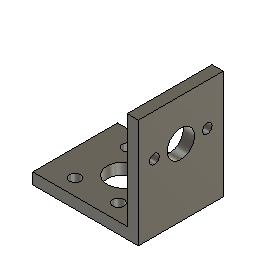
DC motor holder v2 (Autodesk Fusion 360 design; units mm, degrees)
part number: 2026-10-27-13-53-20-862
Autodesk Fusion 360 part; units mm, degrees
sketch "Sketch1" plane through (0, 0, 0) normal (0, 0, 1) x (1, 0, 0)
  line L0 (16.5, -13.25) -> (-16.5, -13.25)
  line L1 (-16.5, -13.25) -> (-16.5, 13.25)
  line L2 (-16.5, 13.25) -> (16.5, 13.25)
  line L3 (16.5, 13.25) -> (16.5, -13.25)
  line L4 (16.5, -13.25) -> (-16.5, 13.25) construction
  line L5 (-16.5, -13.25) -> (16.5, 13.25) construction
  dimension "d1" = 33
  dimension "d2" = 26.5
  constraint horizontal L0
  constraint perpendicular L0 L1
  constraint parallel L0 L2
  constraint parallel L1 L3
  constraint coincident L4 origin
  constraint coincident L5 origin
  measures "d1" distance of L1.end L2.end
  measures "d2" distance of L0.end L1.end
extrude "Extrude1" add sketch "Sketch1" along normal blind 3.5
sketch "Sketch2" plane through (16.5, 0, 0) normal (1, 0, 0) x (0, 1, 0)
  line L0 (-13.25, 0) -> (13.25, 0)
  line L1 (13.25, 0) -> (13.25, 3.5)
  line L2 (13.25, 3.5) -> (-13.25, 3.5)
  line L3 (-13.25, 3.5) -> (-13.25, 0)
  line L4 (-13.25, 0) -> (13.25, 0)
  line L5 (13.25, 0) -> (13.25, 34)
  line L6 (13.25, 34) -> (-13.25, 34)
  line L7 (-13.25, 34) -> (-13.25, 0)
  dimension "d5" = 34
  constraint horizontal L4
  constraint vertical L5
  constraint horizontal L6
  constraint vertical L7
  constraint coincident L0.start L3.end
  measures "d5" distance of L0.start L6.end
extrude "Extrude2" add sketch "Sketch2" against normal blind 3.5 contours L2 L5 L6 L7
sketch "Sketch3" plane through (0, 0, 0) normal (0, 0, -1) x (1, 0, 0)
  line L0 (-16.5, -13.25) -> (16.5, -13.25)
  line L1 (16.5, -13.25) -> (16.5, 13.25)
  line L2 (16.5, 13.25) -> (-16.5, 13.25)
  line L3 (-16.5, 13.25) -> (-16.5, -13.25)
  circle A0 centre (-1.5, 0) radius 5
  circle A1 centre (-8.25, -8.25) radius 1.75
  circle A2 centre (-8.25, 8.25) radius 1.75
  circle A3 centre (5.25, -8.25) radius 1.75
  circle A4 centre (5.25, 8.25) radius 1.75
  dimension "d9" = 10
  dimension "d15" = 3.5
  measures "d9" diameter of A0
  measures "d15" diameter of A1
extrude "Extrude3" cut sketch "Sketch3" against normal blind 9 contours A0 | A1 | A2 | A3 | A4
sketch "Sketch4" plane through (16.5, 0, 0) normal (1, 0, 0) x (0, 1, 0)
  line L0 (-13.25, 0) -> (13.25, 0)
  line L1 (13.25, 0) -> (13.25, 34)
  line L2 (13.25, 34) -> (-13.25, 34)
  line L3 (-13.25, 34) -> (-13.25, 0)
  circle A0 centre (-8.25, 21) radius 1.5
  circle A1 centre (0, 21) radius 4.25
  circle A2 centre (8.25, 21) radius 1.5
  dimension "d24" = 8.5
  measures "d24" diameter of A1
extrude "Extrude4" cut sketch "Sketch4" against normal blind 23 contours A0 | A1 | A2
